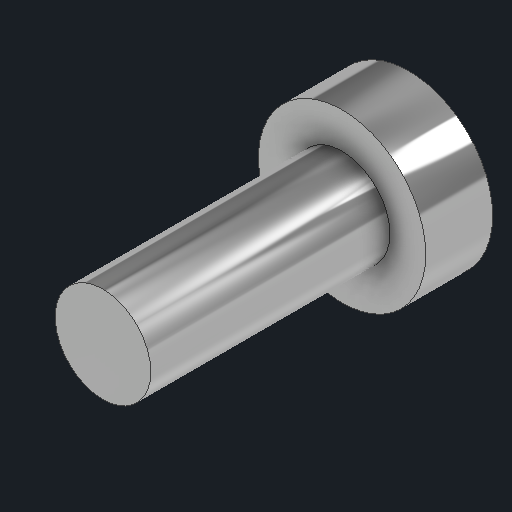
# Autodesk Inventor part: m4_pan_10
Saved by Autodesk Inventor 2027.1 (Build 311270010, 270A)
## iProperties
Created: 2026-11-03
Part Number: m4_pan_10
Material: Generic
Description: M4x10 pan head screw: flat bit bottom-lip screw (photo 23)
Document SubType Name: Modeling
Designer: Claude (from photos)
Density: 1 g/cm^3
Appearance: Stainless Steel - Bright
Author: alexg
Autodesk Inventor part; units mm, degrees
ref_plane "YZ Plane" through (0, 0, 0) normal (1, 0, 0) x (0, 1, 0)
ref_plane "Work Plane1" through (0, 0, -2.8) normal (0, 0, 1) x (1, 0, 0)
sketch "Pan head 7 sketch" plane through (0, 0, -2.8) normal (0, 0, 1) x (1, 0, 0)
  circle A0 centre (0, 0) radius 3.5
  constraints: 1 centre point
extrude "Pan head 7" add sketch "Pan head 7 sketch" along normal blind 2.8
ref_plane "Work Plane2" through (0, 0, -2.8) normal (0, 0, 1) x (1, 0, 0)
sketch "Phillips recess sketch" plane through (0, 0, -2.8) normal (0, 0, 1) x (1, 0, 0)
  line L0 (-2.2, -0.4) -> (2.2, -0.4)
  line L1 (2.2, -0.4) -> (2.2, 0.4)
  line L2 (2.2, 0.4) -> (-2.2, 0.4)
  line L3 (-2.2, 0.4) -> (-2.2, -0.4)
  line L4 (-0.4, -2.2) -> (0.4, -2.2)
  line L5 (0.4, -2.2) -> (0.4, -0.4)
  line L6 (0.4, -0.4) -> (-0.4, -0.4)
  line L7 (-0.4, -0.4) -> (-0.4, -2.2)
  line L8 (-0.4, 0.4) -> (0.4, 0.4)
  line L9 (0.4, 0.4) -> (0.4, 2.2)
  line L10 (0.4, 2.2) -> (-0.4, 2.2)
  line L11 (-0.4, 2.2) -> (-0.4, 0.4)
  constraints: 24 end point, 6 parallel, 3 horizontal, 3 perpendicular
extrude "Phillips recess" cut sketch "Phillips recess sketch" along normal blind 1.4
sketch "Shank M4x10 sketch" plane through (0, 0, 0) normal (0, 0, 1) x (1, 0, 0)
  circle A0 centre (0, 0) radius 2
  constraints: 1 centre point
extrude "Shank M4x10" add sketch "Shank M4x10 sketch" along normal blind 10
body "Solid1"
